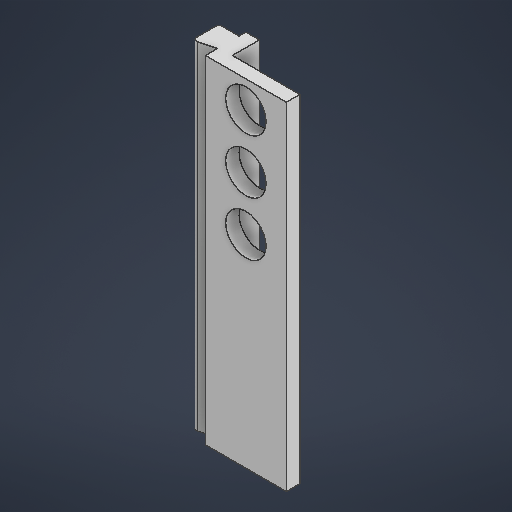
# Autodesk Inventor part: Trafic LED
Saved by Autodesk Inventor 2026.4 (Build 304435000, 435)
## iProperties
Created: 2026-10-05
Part Number: Trafic LED
Material: Generic
Document SubType Name: Modeling
Designer: LENOVO
Density: 1 g/cm^3
Appearance: Default
Author: LENOVO
Autodesk Inventor part; units mm, degrees
ref_plane "YZ Plane" through (0, 0, 0) normal (1, 0, 0) x (0, 1, 0)
ref_plane "XZ Plane" through (0, 0, 0) normal (0, 1, 0) x (-1, 0, 0)
ref_plane "XY Plane" through (0, 0, 0) normal (0, 0, 1) x (1, 0, 0)
sketch "Sketch1" plane through (0, 0, 0) normal (0, 0, 1) x (1, 0, 0)
  line L0 (-6, 25) -> (6, 25)
  line L1 (6, 25) -> (6, -25)
  line L2 (6, -25) -> (-6, -25)
  line L3 (-6, -25) -> (-6, 25)
  line L4 (-6, 25) -> (6, -25) construction
  line L5 (6, 25) -> (-6, -25) construction
  circle A0 centre (0, 21) radius 3
  circle A1 centre (0, 13) radius 3
  circle A2 centre (0, 5) radius 3
  point P0 (0, 0)
  dimension "d0" = 12
  dimension "d1" = 50
  dimension "d2" = 6
  dimension "d3" = 4
  dimension "d4" = 6
  dimension "d5" = 6
  dimension "d6" = 8
  dimension "d7" = 8
  constraints: 12 end point, 3 centre point, 2 midpoint, 2 parallel, 1 horizontal, 1 perpendicular
  measures "d0" distance of L0.start L0.end
  measures "d1" distance of L0.end L1.end
  measures "d2" diameter of A0
  measures "d3" distance from line of L0 A0.centre
  measures "d4" diameter of A1
  measures "d5" diameter of A2
  measures "d6" distance of A0.centre A1.centre
  measures "d7" distance of A1.centre A2.centre
extrude "Extrusion1" add sketch "Sketch1" along normal mid plane 2
sketch "Sketch2" plane through (-6, -25, 1) normal (0, -1, 0) x (1, 0, 0)
  line L0 (12, -2) -> (12, 0) projected
  line L1 (0, 0) -> (12, 0) projected
  line L2 (0, 0) -> (0, -2) projected
  line L3 (12, -2) -> (0, -2) projected
  line L4 (0, -2) -> (0, 0)
  line L5 (2, -6) -> (2, 0)
  line L6 (2, 0) -> (0, 0)
  line L7 (0, 0) -> (0, -6)
  line L8 (0, -1) -> (0, -5)
  line L9 (-3, -1) -> (-3, -4.1962)
  line L10 (-3, -1) -> (-3, -5)
  line L11 (0, -1) -> (0, -4.1962)
  line L12 (-3, -1) -> (0, -1.8038)
  line L13 (-3, -5) -> (0, -4.1962)
  line L14 (-3, -1) -> (0, -1)
  line L15 (-3, -5) -> (0, -5)
  line L16 (2, -6) -> (0, -6)
  point P0 (6, -1)
  point P1 (0, -3)
  point P2 (0, -3)
  point P3 (-3, -3)
  point P4 (-3, -3)
  point P5 (2, -2)
  point P6 (0, -1.8038)
  point P7 (0, -5)
  dimension "d11" = 6
  constraints: 26 end point, 2 midpoint, 2 perpendicular, 1 parallel
  measures "d11" distance of L7.end L7.start
extrude "Extrusion2" add sketch "Sketch2" against normal blind 50 contours L5 L16 L7 L3 | L7 L13 L10 L9 L12 L2 | L7 L15 L13
fillet "Fillet1" radius 0.5 2 edges at (-9, 0, 0) (-9, 0, -4)
body "Solid1"
